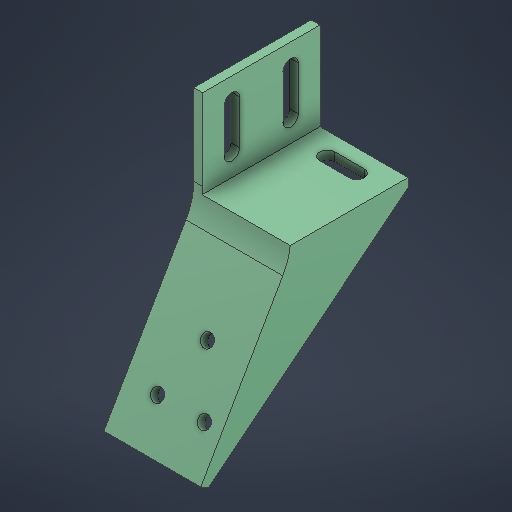
# Autodesk Inventor part: 1_1_7_2_fixation_droite
Saved by Autodesk Inventor 2026 (Build 300175000, 175)
## iProperties
Created: 2025-05-11
Part Number: 1_1_7_2_fixation_droite
Material: Generic
Document SubType Name: Modeling
Designer: remg9
Density: 1 g/cm^3
Appearance: Default
Author: remg9
Autodesk Inventor part; units mm, degrees
ref_plane "YZ Plane" through (0, 0, 0) normal (1, 0, 0) x (0, 1, 0)
ref_plane "XZ Plane" through (0, 0, 0) normal (0, 1, 0) x (-1, 0, 0)
ref_plane "XY Plane" through (0, 0, 0) normal (0, 0, 1) x (1, 0, 0)
sketch "Sketch1" plane through (0, 0, 0) normal (0, 1, 0) x (-1, 0, 0)
  line L0 (-16.5, 20) -> (16.5, 20)
  line L1 (16.5, 20) -> (16.5, -20)
  line L2 (16.5, -20) -> (-16.5, -20)
  line L3 (-16.5, -20) -> (-16.5, 20)
  line L4 (-16.5, 20) -> (16.5, -20) construction
  line L5 (16.5, 20) -> (-16.5, -20) construction
  point P0 (0, 0)
  dimension "d0" = 33
  dimension "d1" = 40
  constraints: 12 end point, 2 midpoint, 2 parallel, 1 horizontal, 1 perpendicular
  measures "d0" distance of L1.end L2.end
  measures "d1" distance of L0.end L1.end
extrude "Extrusion1" add sketch "Sketch1" along normal blind 3
sketch "Sketch2" plane through (0, 3, 0) normal (0, 1, 0) x (1, 0, 0)
  line L0 (-16.5, 20) -> (-16.5, -20) projected
  line L1 (16.5, 20) -> (-16.5, 20) projected
  line L2 (-16.5, -20) -> (-13.5, -20)
  line L3 (-13.5, -20) -> (-13.5, 20)
  line L4 (-13.5, 20) -> (-16.5, 20)
  line L5 (-16.5, 20) -> (-16.5, -20)
  point P0 (0, 0)
  dimension "d4" = 3
  constraints: 8 end point, 2 parallel, 1 horizontal, 1 perpendicular, 1 point on line
  measures "d4" distance between parallel lines of L0 L3
extrude "Extrusion2" add sketch "Sketch2" along normal blind 30
sketch "Sketch3" plane through (0, 0, 0) normal (1, 0, 0) x (0, 1, 0)
  line L0 (0, 20) -> (-53, 50.5996)
  line L1 (-53, 50.5996) -> (-54.5, 48.0015)
  line L2 (0, -20) -> (0, 20) projected
  line L3 (-54.5, 48.0015) -> (0, -20)
  line L4 (0, -20) -> (0, 20)
  line L5 (3, 20) -> (33, 20) projected
  point P0 (0, 0)
  dimension "d8" = 53
  dimension "d9" = 150
  dimension "d10" = 3
  constraints: 8 end point, 1 collinear, 1 perpendicular
  measures "d8" distance from line of L2 L0.end
  measures "d9" angle of L5 L0
  measures "d10" distance of L0.end L1.end
extrude "Extrusion3" add sketch "Sketch3" along normal mid plane 33
sketch "Sketch4" plane through (0, 0, 0) normal (1, 0, 0) x (0, 1, 0)
  line L0 (0, -20) -> (-54.5, 48.0015) projected
  line L1 (0, 16.5359) -> (-54.5, 48.0015)
  line L2 (-54.5, 48.0015) -> (0, -20)
  line L3 (0, -20) -> (0, 16.5359)
  line L4 (-53, 50.5996) -> (0, 20) projected
  point P0 (0, 0)
  constraints: 6 end point, 1 collinear, 1 parallel, 1 vertical
extrude "Extrusion4" cut sketch "Sketch4" along normal mid plane 27
sketch "Sketch5" plane through (-16.5, 0, 20) normal (0, 0.5, 0.866) x (1, 0, 0)
  line L0 (27, -46.6991) -> (11, -46.6991) construction
  line L1 (0, -61.1991) -> (33, -61.1991) projected
  line L2 (33, 0) -> (33, -61.1991) projected
  point P0 (16.5, 10)
  point P1 (19, -28.6991)
  dimension "d15" = 18
  dimension "d16" = 14.5
  dimension "d17" = 6
  dimension "d18" = 16
  dimension "d19" = 14
  constraints: 2 coincident, 2 end point, 1 horizontal
  measures "d15" distance from line of L0 point (19, -28.699)
  measures "d16" distance between parallel lines of L1 L0
  measures "d17" distance from line of L2 L0.start
  measures "d18" distance of L0.start L0.end
  measures "d19" distance from line of L2 point (19, -28.699)
hole "Hole1" at (10.5, -40.4426, 43.3496) at (-5.5, -40.4426, 43.3496) at (2.5, -24.8542, 34.3496) direction (0, -0.5, -0.866) diameter 4.3 end through all
sketch "Sketch6" plane through (-13.5, 0, -20) normal (0, -1, 0) x (1, 0, 0)
  line L0 (10, 7.5) -> (20, 7.5) construction
  line L1 (10, 4.9) -> (20, 4.9)
  line L2 (20, 10.1) -> (10, 10.1)
  arc A0 (10, 10.1) -> (10, 4.9) centre (10, 7.5) ccw
  arc A1 (20, 4.9) -> (20, 10.1) centre (20, 7.5) ccw
  line L3 (0, 0) -> (0, 68.0015) projected
  line L4 (27, 0) -> (0, 0) projected
  point P0 (13.5, 20)
  point P1 (15, 7.5)
  dimension "d27" = 5.2
  dimension "d28" = 15
  dimension "d29" = 10
  dimension "d30" = 7.5
  constraints: 8 end point, 4 point on circle, 4 tangent, 2 centre point, 1 horizontal, 1 midpoint, 1 parallel
  measures "d27" distance between parallel lines of L2 L1
  measures "d28" distance from line of L3 point (15, 7.5)
  measures "d29" distance of L1.start L1.end
  measures "d30" distance from line of L4 point (15, 7.5)
extrude "Extrusion5" cut sketch "Sketch6" against normal through all
fillet "Fillet1" radius 40 1 edges at (0, 0, 16.5359)
fillet "Fillet2" radius 20 1 edges at (0, 0, 20)
fillet "Fillet3" radius 4 3 edges at (-13.5, 0, -13.2791) (-13.5, -5.359, 13.4419) (-13.5, -37.25, 38.0422)
sketch "Sketch7" plane through (-16.5, 33, -20) normal (-1, 0, 0) x (0, 0, 1)
  line L0 (20, 6.7592) -> (20, -33.6647) construction
  line L1 (30, -7.5) -> (30, -22.5) construction
  line L2 (27.4, -7.5) -> (27.4, -22.5)
  line L3 (32.6, -22.5) -> (32.6, -7.5)
  arc A0 (32.6, -7.5) -> (27.4, -7.5) centre (30, -7.5) ccw
  arc A1 (27.4, -22.5) -> (32.6, -22.5) centre (30, -22.5) ccw
  line L4 (0, 0) -> (40, 0) projected
  line L5 (40, -27.641) -> (40, 0) projected
  line L6 (10, -7.5) -> (10, -22.5) construction
  line L7 (12.6, -7.5) -> (12.6, -22.5)
  line L8 (7.4, -22.5) -> (7.4, -7.5)
  arc A2 (12.6, -7.5) -> (7.4, -7.5) centre (10, -7.5) ccw
  arc A3 (7.4, -22.5) -> (12.6, -22.5) centre (10, -22.5) ccw
  point P0 (20, -33)
  point P1 (30, -15)
  point P2 (10, -15)
  dimension "d36" = 5.2
  dimension "d37" = 15
  dimension "d38" = 15
  dimension "d39" = 10
  dimension "d40" = 20
  constraints: 18 end point, 8 point on circle, 7 symmetric about line, 4 centre point, 4 tangent, 2 vertical, 1 midpoint, 1 parallel, 2 other
  measures "d36" distance between parallel lines of L3 L2
  measures "d37" distance of L3.start L3.end
  measures "d38" distance from line of L4 point (30, -15)
  measures "d39" distance from line of L5 point (30, -15)
  measures "d40" distance between parallel lines of L5 L0
extrude "Extrusion6" cut sketch "Sketch7" against normal through all
body "Solid1"
